Autodesk Fusion 360 part; units mm, degrees
(part 4 of 6)
sketch "Sketch2" plane through (0, 1.5, 0) normal (0, 1, 0) x (-1, 0, 0)
  arc A0 (-68.3, 47.105) -> (-68.05, 46.855) centre (-68.05, 47.105) ccw
  line L0 (-68.05, 46.855) -> (-66.4, 46.855)
  arc A1 (-66.15, 46.605) -> (-66.4, 46.855) centre (-66.4, 46.605) ccw
  line L1 (-66.15, 46.605) -> (-66.15, 42.69)
  line L2 (-66.15, 42.69) -> (-64.15, 42.69)
  line L3 (-64.15, 42.69) -> (-64.15, 46.755)
  arc A2 (-63.9, 47.005) -> (-64.15, 46.755) centre (-63.9, 46.755) ccw
  line L4 (-63.9, 47.005) -> (-50.4, 47.005)
  arc A3 (-50.15, 46.755) -> (-50.4, 47.005) centre (-50.4, 46.755) ccw
  line L5 (-50.15, 46.755) -> (-50.15, 42.69)
  line L6 (-50.15, 42.69) -> (-48.15, 42.69)
  line L7 (-48.15, 42.69) -> (-48.15, 46.605)
  arc A4 (-47.9, 46.855) -> (-48.15, 46.605) centre (-47.9, 46.605) ccw
  line L8 (-47.9, 46.855) -> (-46.25, 46.855)
  arc A5 (-46.25, 46.855) -> (-46, 47.105) centre (-46.25, 47.105) ccw
  line L9 (-46, 47.105) -> (-46, 47.605)
  arc A6 (-45.75, 47.855) -> (-46, 47.605) centre (-45.75, 47.605) ccw
  line L10 (-45.75, 47.855) -> (-44.55, 47.855)
  arc A7 (-44.3, 47.605) -> (-44.55, 47.855) centre (-44.55, 47.605) ccw
  line L11 (-44.3, 47.605) -> (-44.3, 47.105)
  arc A8 (-44.3, 47.105) -> (-44.05, 46.855) centre (-44.05, 47.105) ccw
  line L12 (-44.05, 46.855) -> (-42.4, 46.855)
  arc A9 (-42.15, 46.605) -> (-42.4, 46.855) centre (-42.4, 46.605) ccw
  line L13 (-42.15, 46.605) -> (-42.15, 34.605)
  arc A10 (-42.4, 34.355) -> (-42.15, 34.605) centre (-42.4, 34.605) ccw
  line L14 (-42.4, 34.355) -> (-47.9, 34.355)
  arc A11 (-48.15, 34.605) -> (-47.9, 34.355) centre (-47.9, 34.605) ccw
  line L15 (-48.15, 34.605) -> (-48.15, 40.19)
  line L16 (-48.15, 40.19) -> (-50.15, 40.19)
  line L17 (-50.15, 40.19) -> (-50.15, 33.255)
  arc A12 (-50.4, 33.005) -> (-50.15, 33.255) centre (-50.4, 33.255) ccw
  line L18 (-50.4, 33.005) -> (-63.9, 33.005)
  arc A13 (-64.15, 33.255) -> (-63.9, 33.005) centre (-63.9, 33.255) ccw
  line L19 (-64.15, 33.255) -> (-64.15, 40.19)
  line L20 (-64.15, 40.19) -> (-66.15, 40.19)
  line L21 (-66.15, 40.19) -> (-66.15, 34.605)
  arc A14 (-66.4, 34.355) -> (-66.15, 34.605) centre (-66.4, 34.605) ccw
  line L22 (-66.4, 34.355) -> (-71.9, 34.355)
  arc A15 (-72.15, 34.605) -> (-71.9, 34.355) centre (-71.9, 34.605) ccw
  line L23 (-72.15, 34.605) -> (-72.15, 46.605)
  arc A16 (-71.9, 46.855) -> (-72.15, 46.605) centre (-71.9, 46.605) ccw
  line L24 (-71.9, 46.855) -> (-70.25, 46.855)
  arc A17 (-70.25, 46.855) -> (-70, 47.105) centre (-70.25, 47.105) ccw
  line L25 (-70, 47.105) -> (-70, 47.605)
  arc A18 (-69.75, 47.855) -> (-70, 47.605) centre (-69.75, 47.605) ccw
  line L26 (-69.75, 47.855) -> (-68.55, 47.855)
  arc A19 (-68.3, 47.605) -> (-68.55, 47.855) centre (-68.55, 47.605) ccw
  line L27 (-68.3, 47.605) -> (-68.3, 47.105)
  arc A20 (-73.525, 22.33) -> (-73.775, 22.58) centre (-73.775, 22.33) ccw
  line L28 (-73.775, 22.58) -> (-74.275, 22.58)
  arc A21 (-74.525, 22.83) -> (-74.275, 22.58) centre (-74.275, 22.83) ccw
  line L29 (-74.525, 22.83) -> (-74.525, 24.03)
  arc A22 (-74.275, 24.28) -> (-74.525, 24.03) centre (-74.275, 24.03) ccw
  line L30 (-74.275, 24.28) -> (-73.775, 24.28)
  arc A23 (-73.775, 24.28) -> (-73.525, 24.53) centre (-73.775, 24.53) ccw
  line L31 (-73.525, 24.53) -> (-73.525, 26.18)
  arc A24 (-73.275, 26.43) -> (-73.525, 26.18) centre (-73.275, 26.18) ccw
  line L32 (-73.275, 26.43) -> (-61.275, 26.43)
  arc A25 (-61.025, 26.18) -> (-61.275, 26.43) centre (-61.275, 26.18) ccw
  line L33 (-61.025, 26.18) -> (-61.025, 20.68)
  arc A26 (-61.275, 20.43) -> (-61.025, 20.68) centre (-61.275, 20.68) ccw
  line L34 (-61.275, 20.43) -> (-66.86, 20.43)
  line L35 (-66.86, 20.43) -> (-66.86, 18.43)
  line L36 (-66.86, 18.43) -> (-59.925, 18.43)
  arc A27 (-59.675, 18.18) -> (-59.925, 18.43) centre (-59.925, 18.18) ccw
  line L37 (-59.675, 18.18) -> (-59.675, 4.68)
  arc A28 (-59.925, 4.43) -> (-59.675, 4.68) centre (-59.925, 4.68) ccw
  line L38 (-59.925, 4.43) -> (-66.86, 4.43)
  line L39 (-66.86, 4.43) -> (-66.86, 2.43)
  line L40 (-66.86, 2.43) -> (-61.275, 2.43)
  arc A29 (-61.025, 2.18) -> (-61.275, 2.43) centre (-61.275, 2.18) ccw
  line L41 (-61.025, 2.18) -> (-61.025, -3.32)
  arc A30 (-61.275, -3.57) -> (-61.025, -3.32) centre (-61.275, -3.32) ccw
  line L42 (-61.275, -3.57) -> (-73.275, -3.57)
  arc A31 (-73.525, -3.32) -> (-73.275, -3.57) centre (-73.275, -3.32) ccw
  line L43 (-73.525, -3.32) -> (-73.525, -1.67)
  arc A32 (-73.525, -1.67) -> (-73.775, -1.42) centre (-73.775, -1.67) ccw
  line L44 (-73.775, -1.42) -> (-74.275, -1.42)
  arc A33 (-74.525, -1.17) -> (-74.275, -1.42) centre (-74.275, -1.17) ccw
  line L45 (-74.525, -1.17) -> (-74.525, 0.03)
  arc A34 (-74.275, 0.28) -> (-74.525, 0.03) centre (-74.275, 0.03) ccw
  line L46 (-74.275, 0.28) -> (-73.775, 0.28)
  arc A35 (-73.775, 0.28) -> (-73.525, 0.53) centre (-73.775, 0.53) ccw
  line L47 (-73.525, 0.53) -> (-73.525, 2.18)
  arc A36 (-73.275, 2.43) -> (-73.525, 2.18) centre (-73.275, 2.18) ccw
  line L48 (-73.275, 2.43) -> (-69.36, 2.43)
  line L49 (-69.36, 2.43) -> (-69.36, 4.43)
  line L50 (-69.36, 4.43) -> (-73.425, 4.43)
  arc A37 (-73.675, 4.68) -> (-73.425, 4.43) centre (-73.425, 4.68) ccw
  line L51 (-73.675, 4.68) -> (-73.675, 18.18)
  arc A38 (-73.425, 18.43) -> (-73.675, 18.18) centre (-73.425, 18.18) ccw
  line L52 (-73.425, 18.43) -> (-69.36, 18.43)
  line L53 (-69.36, 18.43) -> (-69.36, 20.43)
  line L54 (-69.36, 20.43) -> (-73.275, 20.43)
  arc A39 (-73.525, 20.68) -> (-73.275, 20.43) centre (-73.275, 20.68) ccw
  line L55 (-73.525, 20.68) -> (-73.525, 22.33)
  arc A40 (30.475, 54.725) -> (30.725, 54.475) centre (30.725, 54.725) ccw
  line L56 (30.725, 54.475) -> (32.375, 54.475)
  arc A41 (32.625, 54.225) -> (32.375, 54.475) centre (32.375, 54.225) ccw
  line L57 (32.625, 54.225) -> (32.625, 50.31)
  line L58 (32.625, 50.31) -> (40.625, 50.31)
  line L59 (40.625, 50.31) -> (40.625, 54.375)
  arc A42 (40.875, 54.625) -> (40.625, 54.375) centre (40.875, 54.375) ccw
  line L60 (40.875, 54.625) -> (54.375, 54.625)
  arc A43 (54.625, 54.375) -> (54.375, 54.625) centre (54.375, 54.375) ccw
  line L61 (54.625, 54.375) -> (54.625, 50.31)
  line L62 (54.625, 50.31) -> (62.625, 50.31)
  line L63 (62.625, 50.31) -> (62.625, 54.225)
  arc A44 (62.875, 54.475) -> (62.625, 54.225) centre (62.875, 54.225) ccw
  line L64 (62.875, 54.475) -> (64.525, 54.475)
  arc A45 (64.525, 54.475) -> (64.775, 54.725) centre (64.525, 54.725) ccw
  line L65 (64.775, 54.725) -> (64.775, 55.225)
  arc A46 (65.025, 55.475) -> (64.775, 55.225) centre (65.025, 55.225) ccw
  line L66 (65.025, 55.475) -> (66.225, 55.475)
  arc A47 (66.475, 55.225) -> (66.225, 55.475) centre (66.225, 55.225) ccw
  line L67 (66.475, 55.225) -> (66.475, 54.725)
  arc A48 (66.475, 54.725) -> (66.725, 54.475) centre (66.725, 54.725) ccw
  line L68 (66.725, 54.475) -> (68.375, 54.475)
  arc A49 (68.625, 54.225) -> (68.375, 54.475) centre (68.375, 54.225) ccw
  line L69 (68.625, 54.225) -> (68.625, 42.225)
  arc A50 (68.375, 41.975) -> (68.625, 42.225) centre (68.375, 42.225) ccw
  line L70 (68.375, 41.975) -> (62.875, 41.975)
  arc A51 (62.625, 42.225) -> (62.875, 41.975) centre (62.875, 42.225) ccw
  line L71 (62.625, 42.225) -> (62.625, 47.81)
  line L72 (62.625, 47.81) -> (54.625, 47.81)
  line L73 (54.625, 47.81) -> (54.625, 40.875)
  arc A52 (54.375, 40.625) -> (54.625, 40.875) centre (54.375, 40.875) ccw
  line L74 (54.375, 40.625) -> (40.875, 40.625)
  arc A53 (40.625, 40.875) -> (40.875, 40.625) centre (40.875, 40.875) ccw
  line L75 (40.625, 40.875) -> (40.625, 47.81)
  line L76 (40.625, 47.81) -> (32.625, 47.81)
  line L77 (32.625, 47.81) -> (32.625, 42.225)
  arc A54 (32.375, 41.975) -> (32.625, 42.225) centre (32.375, 42.225) ccw
  line L78 (32.375, 41.975) -> (26.875, 41.975)
  arc A55 (26.625, 42.225) -> (26.875, 41.975) centre (26.875, 42.225) ccw
  line L79 (26.625, 42.225) -> (26.625, 54.225)
  arc A56 (26.875, 54.475) -> (26.625, 54.225) centre (26.875, 54.225) ccw
  line L80 (26.875, 54.475) -> (28.525, 54.475)
  arc A57 (28.525, 54.475) -> (28.775, 54.725) centre (28.525, 54.725) ccw
  line L81 (28.775, 54.725) -> (28.775, 55.225)
  arc A58 (29.025, 55.475) -> (28.775, 55.225) centre (29.025, 55.225) ccw
  line L82 (29.025, 55.475) -> (30.225, 55.475)
  arc A59 (30.475, 55.225) -> (30.225, 55.475) centre (30.225, 55.225) ccw
  line L83 (30.475, 55.225) -> (30.475, 54.725)
  line L84 (-21.825, 33.005) -> (-35.325, 33.005)
  arc A60 (-35.575, 33.255) -> (-35.325, 33.005) centre (-35.325, 33.255) ccw
  line L85 (-35.575, 33.255) -> (-35.575, 46.755)
  arc A61 (-35.325, 47.005) -> (-35.575, 46.755) centre (-35.325, 46.755) ccw
  line L86 (-35.325, 47.005) -> (-21.825, 47.005)
  arc A62 (-21.575, 46.755) -> (-21.825, 47.005) centre (-21.825, 46.755) ccw
  line L87 (-21.575, 46.755) -> (-21.575, 33.255)
  arc A63 (-21.825, 33.005) -> (-21.575, 33.255) centre (-21.825, 33.255) ccw
  line L88 (43.9638, 101.8458) -> (47.4579, 88.8058)
  arc A64 (47.2811, 88.4996) -> (47.4579, 88.8058) centre (47.2164, 88.7411) ccw
  line L89 (47.2811, 88.4996) -> (34.2411, 85.0056)
  arc A65 (33.9349, 85.1824) -> (34.2411, 85.0056) centre (34.1764, 85.2471) ccw
  line L90 (33.9349, 85.1824) -> (30.4408, 98.2224)
  arc A66 (30.6176, 98.5285) -> (30.4408, 98.2224) centre (30.6823, 98.2871) ccw
  line L91 (30.6176, 98.5285) -> (43.6576, 102.0226)
  arc A67 (43.9638, 101.8458) -> (43.6576, 102.0226) centre (43.7223, 101.7811) ccw
  line L92 (35.325, -22.24) -> (21.825, -22.24)
  arc A68 (21.575, -21.99) -> (21.825, -22.24) centre (21.825, -21.99) ccw
  line L93 (21.575, -21.99) -> (21.575, -8.49)
  arc A69 (21.825, -8.24) -> (21.575, -8.49) centre (21.825, -8.49) ccw
  line L94 (21.825, -8.24) -> (35.325, -8.24)
  arc A70 (35.575, -8.49) -> (35.325, -8.24) centre (35.325, -8.49) ccw
  line L95 (35.575, -8.49) -> (35.575, -21.99)
  arc A71 (35.325, -22.24) -> (35.575, -21.99) centre (35.325, -21.99) ccw
  line L96 (-16.525, -42.945) -> (-16.525, -29.445)
  arc A72 (-16.275, -29.195) -> (-16.525, -29.445) centre (-16.275, -29.445) ccw
  line L97 (-16.275, -29.195) -> (-2.775, -29.195)
  arc A73 (-2.525, -29.445) -> (-2.775, -29.195) centre (-2.775, -29.445) ccw
  line L98 (-2.525, -29.445) -> (-2.525, -42.945)
  arc A74 (-2.775, -43.195) -> (-2.525, -42.945) centre (-2.775, -42.945) ccw
  line L99 (-2.775, -43.195) -> (-16.275, -43.195)
  arc A75 (-16.525, -42.945) -> (-16.275, -43.195) centre (-16.275, -42.945) ccw
  line L100 (-21.825, -24.145) -> (-35.325, -24.145)
  arc A76 (-35.575, -23.895) -> (-35.325, -24.145) centre (-35.325, -23.895) ccw
  line L101 (-35.575, -23.895) -> (-35.575, -10.395)
  arc A77 (-35.325, -10.145) -> (-35.575, -10.395) centre (-35.325, -10.395) ccw
  line L102 (-35.325, -10.145) -> (-21.825, -10.145)
  arc A78 (-21.575, -10.395) -> (-21.825, -10.145) centre (-21.825, -10.395) ccw
  line L103 (-21.575, -10.395) -> (-21.575, -23.895)
  arc A79 (-21.825, -24.145) -> (-21.575, -23.895) centre (-21.825, -23.895) ccw
  line L104 (-40.875, 13.955) -> (-54.375, 13.955)
  arc A80 (-54.625, 14.205) -> (-54.375, 13.955) centre (-54.375, 14.205) ccw
  line L105 (-54.625, 14.205) -> (-54.625, 27.705)
  arc A81 (-54.375, 27.955) -> (-54.625, 27.705) centre (-54.375, 27.705) ccw
  line L106 (-54.375, 27.955) -> (-40.875, 27.955)
  arc A82 (-40.625, 27.705) -> (-40.875, 27.955) centre (-40.875, 27.705) ccw
  line L107 (-40.625, 27.705) -> (-40.625, 14.205)
  arc A83 (-40.875, 13.955) -> (-40.625, 14.205) centre (-40.875, 14.205) ccw
  line L108 (21.575, -60.09) -> (21.575, -46.59)
  arc A84 (21.825, -46.34) -> (21.575, -46.59) centre (21.825, -46.59) ccw
  line L109 (21.825, -46.34) -> (35.325, -46.34)
  arc A85 (35.575, -46.59) -> (35.325, -46.34) centre (35.325, -46.59) ccw
  line L110 (35.575, -46.59) -> (35.575, -60.09)
  arc A86 (35.325, -60.34) -> (35.575, -60.09) centre (35.325, -60.09) ccw
  line L111 (35.325, -60.34) -> (21.825, -60.34)
  arc A87 (21.575, -60.09) -> (21.825, -60.34) centre (21.825, -60.09) ccw
  line L112 (25.5629, 96.9153) -> (29.057, 83.8753)
  arc A88 (28.8802, 83.5691) -> (29.057, 83.8753) centre (28.8155, 83.8106) ccw
  line L113 (28.8802, 83.5691) -> (15.8402, 80.0751)
  arc A89 (15.534, 80.2519) -> (15.8402, 80.0751) centre (15.7755, 80.3166) ccw
  line L114 (15.534, 80.2519) -> (12.0399, 93.2919)
  arc A90 (12.2167, 93.598) -> (12.0399, 93.2919) centre (12.2814, 93.3566) ccw
  line L115 (12.2167, 93.598) -> (25.2567, 97.0921)
  arc A91 (25.5629, 96.9153) -> (25.2567, 97.0921) centre (25.3214, 96.8506) ccw
  line L116 (35.325, 15.86) -> (21.825, 15.86)
  arc A92 (21.575, 16.11) -> (21.825, 15.86) centre (21.825, 16.11) ccw
  line L117 (21.575, 16.11) -> (21.575, 29.61)
  arc A93 (21.825, 29.86) -> (21.575, 29.61) centre (21.825, 29.61) ccw
  line L118 (21.825, 29.86) -> (35.325, 29.86)
  arc A94 (35.575, 29.61) -> (35.325, 29.86) centre (35.325, 29.61) ccw
  line L119 (35.575, 29.61) -> (35.575, 16.11)
  arc A95 (35.325, 15.86) -> (35.575, 16.11) centre (35.325, 16.11) ccw
  line L120 (-59.925, -24.145) -> (-73.425, -24.145)
  arc A96 (-73.675, -23.895) -> (-73.425, -24.145) centre (-73.425, -23.895) ccw
  line L121 (-73.675, -23.895) -> (-73.675, -10.395)
  arc A97 (-73.425, -10.145) -> (-73.675, -10.395) centre (-73.425, -10.395) ccw
  line L122 (-73.425, -10.145) -> (-59.925, -10.145)
  arc A98 (-59.675, -10.395) -> (-59.925, -10.145) centre (-59.925, -10.395) ccw
  line L123 (-59.675, -10.395) -> (-59.675, -23.895)
  arc A99 (-59.925, -24.145) -> (-59.675, -23.895) centre (-59.925, -23.895) ccw
  line L124 (54.375, -54.625) -> (40.875, -54.625)
  arc A100 (40.625, -54.375) -> (40.875, -54.625) centre (40.875, -54.375) ccw
  line L125 (40.625, -54.375) -> (40.625, -40.875)
  arc A101 (40.875, -40.625) -> (40.625, -40.875) centre (40.875, -40.875) ccw
  line L126 (40.875, -40.625) -> (54.375, -40.625)
  arc A102 (54.625, -40.875) -> (54.375, -40.625) centre (54.375, -40.875) ccw
  line L127 (54.625, -40.875) -> (54.625, -54.375)
  arc A103 (54.375, -54.625) -> (54.625, -54.375) centre (54.375, -54.375) ccw
  line L128 (-2.775, -24.145) -> (-16.275, -24.145)
  arc A104 (-16.525, -23.895) -> (-16.275, -24.145) centre (-16.275, -23.895) ccw
  line L129 (-16.525, -23.895) -> (-16.525, -10.395)
  arc A105 (-16.275, -10.145) -> (-16.525, -10.395) centre (-16.275, -10.395) ccw
  line L130 (-16.275, -10.145) -> (-2.775, -10.145)
  arc A106 (-2.525, -10.395) -> (-2.775, -10.145) centre (-2.775, -10.395) ccw
  line L131 (-2.525, -10.395) -> (-2.525, -23.895)
  arc A107 (-2.775, -24.145) -> (-2.525, -23.895) centre (-2.775, -23.895) ccw
  line L132 (-2.775, 13.955) -> (-16.275, 13.955)
  arc A108 (-16.525, 14.205) -> (-16.275, 13.955) centre (-16.275, 14.205) ccw
  line L133 (-16.525, 14.205) -> (-16.525, 27.705)
  arc A109 (-16.275, 27.955) -> (-16.525, 27.705) centre (-16.275, 27.705) ccw
  line L134 (-16.275, 27.955) -> (-2.775, 27.955)
  arc A110 (-2.525, 27.705) -> (-2.775, 27.955) centre (-2.775, 27.705) ccw
  line L135 (-2.525, 27.705) -> (-2.525, 14.205)
  arc A111 (-2.775, 13.955) -> (-2.525, 14.205) centre (-2.775, 14.205) ccw
  line L136 (54.375, -16.525) -> (40.875, -16.525)
  arc A112 (40.625, -16.275) -> (40.875, -16.525) centre (40.875, -16.275) ccw
  line L137 (40.625, -16.275) -> (40.625, -2.775)
  arc A113 (40.875, -2.525) -> (40.625, -2.775) centre (40.875, -2.775) ccw
  line L138 (40.875, -2.525) -> (54.375, -2.525)
  arc A114 (54.625, -2.775) -> (54.375, -2.525) centre (54.375, -2.775) ccw
  line L139 (54.625, -2.775) -> (54.625, -16.275)
  arc A115 (54.375, -16.525) -> (54.625, -16.275) centre (54.375, -16.275) ccw
  line L140 (-2.775, 33.005) -> (-16.275, 33.005)
  arc A116 (-16.525, 33.255) -> (-16.275, 33.005) centre (-16.275, 33.255) ccw
  line L141 (-16.525, 33.255) -> (-16.525, 46.755)
  arc A117 (-16.275, 47.005) -> (-16.525, 46.755) centre (-16.275, 46.755) ccw
  line L142 (-16.275, 47.005) -> (-2.775, 47.005)
  arc A118 (-2.525, 46.755) -> (-2.775, 47.005) centre (-2.775, 46.755) ccw
  line L143 (-2.525, 46.755) -> (-2.525, 33.255)
  arc A119 (-2.775, 33.005) -> (-2.525, 33.255) centre (-2.775, 33.255) ccw
  line L144 (48.8943, 83.4449) -> (52.3884, 70.4049)
  arc A120 (52.2116, 70.0988) -> (52.3884, 70.4049) centre (52.1469, 70.3402) ccw
  line L145 (52.2116, 70.0988) -> (39.1716, 66.6047)
  arc A121 (38.8654, 66.7815) -> (39.1716, 66.6047) centre (39.1069, 66.8462) ccw
  line L146 (38.8654, 66.7815) -> (35.3713, 79.8215)
  arc A122 (35.5481, 80.1277) -> (35.3713, 79.8215) centre (35.6128, 79.8862) ccw
  line L147 (35.5481, 80.1277) -> (48.5881, 83.6217)
  arc A123 (48.8943, 83.4449) -> (48.5881, 83.6217) centre (48.6528, 83.3802) ccw
  line L148 (-59.925, -43.195) -> (-73.425, -43.195)
  arc A124 (-73.675, -42.945) -> (-73.425, -43.195) centre (-73.425, -42.945) ccw
  line L149 (-73.675, -42.945) -> (-73.675, -29.445)
  arc A125 (-73.425, -29.195) -> (-73.675, -29.445) centre (-73.425, -29.445) ccw
  line L150 (-73.425, -29.195) -> (-59.925, -29.195)
  arc A126 (-59.675, -29.445) -> (-59.925, -29.195) centre (-59.925, -29.445) ccw
  line L151 (-59.675, -29.445) -> (-59.675, -42.945)
  arc A127 (-59.925, -43.195) -> (-59.675, -42.945) centre (-59.925, -42.945) ccw
  line L152 (16.275, -14.62) -> (2.775, -14.62)
  arc A128 (2.525, -14.37) -> (2.775, -14.62) centre (2.775, -14.37) ccw
  line L153 (2.525, -14.37) -> (2.525, -0.87)
  arc A129 (2.775, -0.62) -> (2.525, -0.87) centre (2.775, -0.87) ccw
  line L154 (2.775, -0.62) -> (16.275, -0.62)
  arc A130 (16.525, -0.87) -> (16.275, -0.62) centre (16.275, -0.87) ccw
  line L155 (16.525, -0.87) -> (16.525, -14.37)
  arc A131 (16.275, -14.62) -> (16.525, -14.37) centre (16.275, -14.37) ccw
  line L156 (-21.825, 13.955) -> (-35.325, 13.955)
  arc A132 (-35.575, 14.205) -> (-35.325, 13.955) centre (-35.325, 14.205) ccw
  line L157 (-35.575, 14.205) -> (-35.575, 27.705)
  arc A133 (-35.325, 27.955) -> (-35.575, 27.705) centre (-35.325, 27.705) ccw
  line L158 (-35.325, 27.955) -> (-21.825, 27.955)
  arc A134 (-21.575, 27.705) -> (-21.825, 27.955) centre (-21.825, 27.705) ccw
  line L159 (-21.575, 27.705) -> (-21.575, 14.205)
  arc A135 (-21.825, 13.955) -> (-21.575, 14.205) centre (-21.825, 14.205) ccw
  line L160 (-54.625, -4.845) -> (-54.625, 8.655)
  arc A136 (-54.375, 8.905) -> (-54.625, 8.655) centre (-54.375, 8.655) ccw
  line L161 (-54.375, 8.905) -> (-40.875, 8.905)
  arc A137 (-40.625, 8.655) -> (-40.875, 8.905) centre (-40.875, 8.655) ccw
  line L162 (-40.625, 8.655) -> (-40.625, -4.845)
  arc A138 (-40.875, -5.095) -> (-40.625, -4.845) centre (-40.875, -4.845) ccw
  line L163 (-40.875, -5.095) -> (-54.375, -5.095)
  arc A139 (-54.625, -4.845) -> (-54.375, -5.095) centre (-54.375, -4.845) ccw
  line L164 (86.56, 59.625) -> (84.594, 73.5992)
  line L165 (84.594, 73.5992) -> (73.4518, 115.1823)
  line L166 (73.4518, 115.1823) -> (5.8515, 97.0689)
  line L167 (5.8515, 97.0689) -> (2.475, 71.055)
  line L168 (2.475, 71.055) -> (-59.625, 71.055)
  line L169 (-59.625, 71.055) -> (-59.625, 52.005)
  line L170 (-59.625, 52.005) -> (-78.675, 52.005)
  line L171 (-78.675, 52.005) -> (-78.675, -48.195)
  line L172 (-78.675, -48.195) -> (-2.475, -48.195)
  line L173 (-2.475, -48.195) -> (-2.475, -57.72)
  line L174 (-2.475, -57.72) -> (16.575, -57.72)
  line L175 (16.575, -57.72) -> (16.575, -65.34)
  line L176 (16.575, -65.34) -> (40.575, -65.34)
  line L177 (40.575, -65.34) -> (40.575, -59.625)
  line L178 (40.575, -59.625) -> (86.56, -59.625)
  line L179 (86.56, -59.625) -> (86.56, 59.625)
  line L180 (35.325, -41.29) -> (21.825, -41.29)
  arc A140 (21.575, -41.04) -> (21.825, -41.29) centre (21.825, -41.04) ccw
  line L181 (21.575, -41.04) -> (21.575, -27.54)
  arc A141 (21.825, -27.29) -> (21.575, -27.54) centre (21.825, -27.54) ccw
  line L182 (21.825, -27.29) -> (35.325, -27.29)
  arc A142 (35.575, -27.54) -> (35.325, -27.29) centre (35.325, -27.54) ccw
  line L183 (35.575, -27.54) -> (35.575, -41.04)
  arc A143 (35.325, -41.29) -> (35.575, -41.04) centre (35.325, -41.04) ccw
  line L184 (16.275, 23.48) -> (2.775, 23.48)
  arc A144 (2.525, 23.73) -> (2.775, 23.48) centre (2.775, 23.73) ccw
  line L185 (2.525, 23.73) -> (2.525, 37.23)
  arc A145 (2.775, 37.48) -> (2.525, 37.23) centre (2.775, 37.23) ccw
  line L186 (2.775, 37.48) -> (16.275, 37.48)
  arc A146 (16.525, 37.23) -> (16.275, 37.48) centre (16.275, 37.23) ccw
  line L187 (16.525, 37.23) -> (16.525, 23.73)
  arc A147 (16.275, 23.48) -> (16.525, 23.73) centre (16.275, 23.73) ccw
  line L188 (-2.775, -5.095) -> (-16.275, -5.095)
  arc A148 (-16.525, -4.845) -> (-16.275, -5.095) centre (-16.275, -4.845) ccw
  line L189 (-16.525, -4.845) -> (-16.525, 8.655)
  arc A149 (-16.275, 8.905) -> (-16.525, 8.655) centre (-16.275, 8.655) ccw
  line L190 (-16.275, 8.905) -> (-2.775, 8.905)
  arc A150 (-2.525, 8.655) -> (-2.775, 8.905) centre (-2.775, 8.655) ccw
  line L191 (-2.525, 8.655) -> (-2.525, -4.845)
  arc A151 (-2.775, -5.095) -> (-2.525, -4.845) centre (-2.775, -4.845) ccw
  line L192 (-21.825, -5.095) -> (-35.325, -5.095)
  arc A152 (-35.575, -4.845) -> (-35.325, -5.095) centre (-35.325, -4.845) ccw
  line L193 (-35.575, -4.845) -> (-35.575, 8.655)
  arc A153 (-35.325, 8.905) -> (-35.575, 8.655) centre (-35.325, 8.655) ccw
  line L194 (-35.325, 8.905) -> (-21.825, 8.905)
  arc A154 (-21.575, 8.655) -> (-21.825, 8.905) centre (-21.825, 8.655) ccw
  line L195 (-21.575, 8.655) -> (-21.575, -4.845)
  arc A155 (-21.825, -5.095) -> (-21.575, -4.845) centre (-21.825, -4.845) ccw
  line L196 (73.425, 21.575) -> (59.925, 21.575)
  arc A156 (59.675, 21.825) -> (59.925, 21.575) centre (59.925, 21.825) ccw
  line L197 (59.675, 21.825) -> (59.675, 35.325)
  arc A157 (59.925, 35.575) -> (59.675, 35.325) centre (59.925, 35.325) ccw
  line L198 (59.925, 35.575) -> (73.425, 35.575)
  arc A158 (73.675, 35.325) -> (73.425, 35.575) centre (73.425, 35.325) ccw
  line L199 (73.675, 35.325) -> (73.675, 21.825)
  arc A159 (73.425, 21.575) -> (73.675, 21.825) centre (73.425, 21.825) ccw
  line L200 (73.425, -16.525) -> (59.925, -16.525)
  arc A160 (59.675, -16.275) -> (59.925, -16.525) centre (59.925, -16.275) ccw
  line L201 (59.675, -16.275) -> (59.675, -2.775)
  arc A161 (59.925, -2.525) -> (59.675, -2.775) centre (59.925, -2.775) ccw
  line L202 (59.925, -2.525) -> (73.425, -2.525)
  arc A162 (73.675, -2.775) -> (73.425, -2.525) centre (73.425, -2.775) ccw
  line L203 (73.675, -2.775) -> (73.675, -16.275)
  arc A163 (73.425, -16.525) -> (73.675, -16.275) centre (73.425, -16.275) ccw
  line L204 (54.375, 21.575) -> (40.875, 21.575)
  arc A164 (40.625, 21.825) -> (40.875, 21.575) centre (40.875, 21.825) ccw
  line L205 (40.625, 21.825) -> (40.625, 35.325)
  arc A165 (40.875, 35.575) -> (40.625, 35.325) centre (40.875, 35.325) ccw
  line L206 (40.875, 35.575) -> (54.375, 35.575)
  arc A166 (54.625, 35.325) -> (54.375, 35.575) centre (54.375, 35.325) ccw
  line L207 (54.625, 35.325) -> (54.625, 21.825)
  arc A167 (54.375, 21.575) -> (54.625, 21.825) centre (54.375, 21.825) ccw
  line L208 (-54.625, -42.945) -> (-54.625, -29.445)
  arc A168 (-54.375, -29.195) -> (-54.625, -29.445) centre (-54.375, -29.445) ccw
  line L209 (-54.375, -29.195) -> (-40.875, -29.195)
  arc A169 (-40.625, -29.445) -> (-40.875, -29.195) centre (-40.875, -29.445) ccw
  line L210 (-40.625, -29.445) -> (-40.625, -42.945)
  arc A170 (-40.875, -43.195) -> (-40.625, -42.945) centre (-40.875, -42.945) ccw
  line L211 (-40.875, -43.195) -> (-54.375, -43.195)
  arc A171 (-54.625, -42.945) -> (-54.375, -43.195) centre (-54.375, -42.945) ccw
  line L212 (2.525, -52.47) -> (2.525, -38.72)
  line L213 (2.525, -38.72) -> (16.275, -38.72)
  arc A172 (16.525, -38.97) -> (16.275, -38.72) centre (16.275, -38.97) ccw
  line L214 (16.525, -38.97) -> (16.525, -52.47)
  arc A173 (16.275, -52.72) -> (16.525, -52.47) centre (16.275, -52.47) ccw
  line L215 (16.275, -52.72) -> (2.775, -52.72)
  arc A174 (2.525, -52.47) -> (2.775, -52.72) centre (2.775, -52.47) ccw
  line L216 (54.375, 2.525) -> (40.875, 2.525)
  arc A175 (40.625, 2.775) -> (40.875, 2.525) centre (40.875, 2.775) ccw
  line L217 (40.625, 2.775) -> (40.625, 16.275)
  arc A176 (40.875, 16.525) -> (40.625, 16.275) centre (40.875, 16.275) ccw
  line L218 (40.875, 16.525) -> (54.375, 16.525)
  arc A177 (54.625, 16.275) -> (54.375, 16.525) centre (54.375, 16.275) ccw
  line L219 (54.625, 16.275) -> (54.625, 2.775)
  arc A178 (54.375, 2.525) -> (54.625, 2.775) centre (54.375, 2.775) ccw
  line L220 (16.275, 42.53) -> (2.775, 42.53)
  arc A179 (2.525, 42.78) -> (2.775, 42.53) centre (2.775, 42.78) ccw
  line L221 (2.525, 42.78) -> (2.525, 56.28)
  arc A180 (2.775, 56.53) -> (2.525, 56.28) centre (2.775, 56.28) ccw
  line L222 (2.775, 56.53) -> (16.275, 56.53)
  arc A181 (16.525, 56.28) -> (16.275, 56.53) centre (16.275, 56.28) ccw
  line L223 (16.525, 56.28) -> (16.525, 42.78)
  arc A182 (16.275, 42.53) -> (16.525, 42.78) centre (16.275, 42.78) ccw
  line L224 (73.425, 2.525) -> (59.925, 2.525)
  arc A183 (59.675, 2.775) -> (59.925, 2.525) centre (59.925, 2.775) ccw
  line L225 (59.675, 2.775) -> (59.675, 16.275)
  arc A184 (59.925, 16.525) -> (59.675, 16.275) centre (59.925, 16.275) ccw
  line L226 (59.925, 16.525) -> (73.425, 16.525)
  arc A185 (73.675, 16.275) -> (73.425, 16.525) centre (73.425, 16.275) ccw
  line L227 (73.675, 16.275) -> (73.675, 2.775)
  arc A186 (73.425, 2.525) -> (73.675, 2.775) centre (73.425, 2.775) ccw
  line L228 (20.4645, 61.851) -> (16.9705, 74.891)
  arc A187 (17.1472, 75.1972) -> (16.9705, 74.891) centre (17.2119, 74.9557) ccw
  line L229 (17.1472, 75.1972) -> (30.1872, 78.6912)
  arc A188 (30.4934, 78.5144) -> (30.1872, 78.6912) centre (30.2519, 78.4497) ccw
  line L230 (30.4934, 78.5144) -> (33.9875, 65.4744)
  arc A189 (33.8107, 65.1683) -> (33.9875, 65.4744) centre (33.746, 65.4097) ccw
  line L231 (33.8107, 65.1683) -> (20.7707, 61.6742)
  arc A190 (20.4645, 61.851) -> (20.7707, 61.6742) centre (20.706, 61.9157) ccw
  line L232 (-21.825, 52.055) -> (-35.325, 52.055)
  arc A191 (-35.575, 52.305) -> (-35.325, 52.055) centre (-35.325, 52.305) ccw
  line L233 (-35.575, 52.305) -> (-35.575, 65.805)
  arc A192 (-35.325, 66.055) -> (-35.575, 65.805) centre (-35.325, 65.805) ccw
  line L234 (-35.325, 66.055) -> (-21.825, 66.055)
  arc A193 (-21.575, 65.805) -> (-21.825, 66.055) centre (-21.825, 65.805) ccw
  line L235 (-21.575, 65.805) -> (-21.575, 52.305)
  arc A194 (-21.825, 52.055) -> (-21.575, 52.305) centre (-21.825, 52.305) ccw
  line L236 (35.325, -3.19) -> (21.825, -3.19)
  arc A195 (21.575, -2.94) -> (21.825, -3.19) centre (21.825, -2.94) ccw
  line L237 (21.575, -2.94) -> (21.575, 10.56)
  arc A196 (21.825, 10.81) -> (21.575, 10.56) centre (21.825, 10.56) ccw
  line L238 (21.825, 10.81) -> (35.325, 10.81)
  arc A197 (35.575, 10.56) -> (35.325, 10.81) centre (35.325, 10.56) ccw
  line L239 (35.575, 10.56) -> (35.575, -2.94)
  arc A198 (35.325, -3.19) -> (35.575, -2.94) centre (35.325, -2.94) ccw
  line L240 (-21.825, -43.195) -> (-35.325, -43.195)
  arc A199 (-35.575, -42.945) -> (-35.325, -43.195) centre (-35.325, -42.945) ccw
  line L241 (-35.575, -42.945) -> (-35.575, -29.445)
  arc A200 (-35.325, -29.195) -> (-35.575, -29.445) centre (-35.325, -29.445) ccw
  line L242 (-35.325, -29.195) -> (-21.825, -29.195)
  arc A201 (-21.575, -29.445) -> (-21.825, -29.195) centre (-21.825, -29.445) ccw
  line L243 (-21.575, -29.445) -> (-21.575, -42.945)
  arc A202 (-21.825, -43.195) -> (-21.575, -42.945) centre (-21.825, -42.945) ccw
  line L244 (59.675, -54.375) -> (59.675, -40.875)
  arc A203 (59.925, -40.625) -> (59.675, -40.875) centre (59.925, -40.875) ccw
  line L245 (59.925, -40.625) -> (73.425, -40.625)
  arc A204 (73.675, -40.875) -> (73.425, -40.625) centre (73.425, -40.875) ccw
  line L246 (73.675, -40.875) -> (73.675, -54.375)
  arc A205 (73.425, -54.625) -> (73.675, -54.375) centre (73.425, -54.375) ccw
  line L247 (73.425, -54.625) -> (59.925, -54.625)
  arc A206 (59.675, -54.375) -> (59.925, -54.625) centre (59.925, -54.375) ccw
  line L248 (16.275, 4.43) -> (2.775, 4.43)
  arc A207 (2.525, 4.68) -> (2.775, 4.43) centre (2.775, 4.68) ccw
  line L249 (2.525, 4.68) -> (2.525, 18.18)
  arc A208 (2.775, 18.43) -> (2.525, 18.18) centre (2.775, 18.18) ccw
  line L250 (2.775, 18.43) -> (16.275, 18.43)
  arc A209 (16.525, 18.18) -> (16.275, 18.43) centre (16.275, 18.18) ccw
  line L251 (16.525, 18.18) -> (16.525, 4.68)
  arc A210 (16.275, 4.43) -> (16.525, 4.68) centre (16.275, 4.68) ccw
  line L252 (16.275, -33.67) -> (2.775, -33.67)
  arc A211 (2.525, -33.42) -> (2.775, -33.67) centre (2.775, -33.42) ccw
  line L253 (2.525, -33.42) -> (2.525, -19.92)
  arc A212 (2.775, -19.67) -> (2.525, -19.92) centre (2.775, -19.92) ccw
  line L254 (2.775, -19.67) -> (16.275, -19.67)
  arc A213 (16.525, -19.92) -> (16.275, -19.67) centre (16.275, -19.92) ccw
  line L255 (16.525, -19.92) -> (16.525, -33.42)
  arc A214 (16.275, -33.67) -> (16.525, -33.42) centre (16.275, -33.42) ccw
  line L256 (-2.775, 52.055) -> (-16.275, 52.055)
  arc A215 (-16.525, 52.305) -> (-16.275, 52.055) centre (-16.275, 52.305) ccw
  line L257 (-16.525, 52.305) -> (-16.525, 65.805)
  arc A216 (-16.275, 66.055) -> (-16.525, 65.805) centre (-16.275, 65.805) ccw
  line L258 (-16.275, 66.055) -> (-2.775, 66.055)
  arc A217 (-2.525, 65.805) -> (-2.775, 66.055) centre (-2.775, 65.805) ccw
  line L259 (-2.525, 65.805) -> (-2.525, 52.305)
  arc A218 (-2.775, 52.055) -> (-2.525, 52.305) centre (-2.775, 52.305) ccw
  line L260 (54.375, -35.575) -> (40.875, -35.575)
  arc A219 (40.625, -35.325) -> (40.875, -35.575) centre (40.875, -35.325) ccw
  line L261 (40.625, -35.325) -> (40.625, -21.825)
  arc A220 (40.875, -21.575) -> (40.625, -21.825) centre (40.875, -21.825) ccw
  line L262 (40.875, -21.575) -> (54.375, -21.575)
  arc A221 (54.625, -21.825) -> (54.375, -21.575) centre (54.375, -21.825) ccw
  line L263 (54.625, -21.825) -> (54.625, -35.325)
  arc A222 (54.375, -35.575) -> (54.625, -35.325) centre (54.375, -35.325) ccw
  line L264 (67.2952, 88.3754) -> (70.7892, 75.3354)
  arc A223 (70.6125, 75.0293) -> (70.7892, 75.3354) centre (70.5478, 75.2707) ccw
  line L265 (70.6125, 75.0293) -> (57.5725, 71.5352)
  arc A224 (57.2663, 71.712) -> (57.5725, 71.5352) centre (57.5078, 71.7767) ccw
  line L266 (57.2663, 71.712) -> (53.7722, 84.752)
  arc A225 (53.949, 85.0582) -> (53.7722, 84.752) centre (54.0137, 84.8167) ccw
  line L267 (53.949, 85.0582) -> (66.989, 88.5522)
  arc A226 (67.2952, 88.3754) -> (66.989, 88.5522) centre (67.0537, 88.3107) ccw
  line L268 (-40.875, -24.145) -> (-54.375, -24.145)
  arc A227 (-54.625, -23.895) -> (-54.375, -24.145) centre (-54.375, -23.895) ccw
  line L269 (-54.625, -23.895) -> (-54.625, -10.395)
  arc A228 (-54.375, -10.145) -> (-54.625, -10.395) centre (-54.375, -10.395) ccw
  line L270 (-54.375, -10.145) -> (-40.875, -10.145)
  arc A229 (-40.625, -10.395) -> (-40.875, -10.145) centre (-40.875, -10.395) ccw
  line L271 (-40.625, -10.395) -> (-40.625, -23.895)
  arc A230 (-40.875, -24.145) -> (-40.625, -23.895) centre (-40.875, -23.895) ccw
  line L272 (-54.625, 52.305) -> (-54.625, 65.805)
  arc A231 (-54.375, 66.055) -> (-54.625, 65.805) centre (-54.375, 65.805) ccw
  line L273 (-54.375, 66.055) -> (-40.875, 66.055)
  arc A232 (-40.625, 65.805) -> (-40.875, 66.055) centre (-40.875, 65.805) ccw
  line L274 (-40.625, 65.805) -> (-40.625, 52.305)
  arc A233 (-40.875, 52.055) -> (-40.625, 52.305) centre (-40.875, 52.305) ccw
  line L275 (-40.875, 52.055) -> (-54.375, 52.055)
  arc A234 (-54.625, 52.305) -> (-54.375, 52.055) centre (-54.375, 52.305) ccw
  line L276 (73.425, -35.575) -> (59.925, -35.575)
  arc A235 (59.675, -35.325) -> (59.925, -35.575) centre (59.925, -35.325) ccw
  line L277 (59.675, -35.325) -> (59.675, -21.825)
  arc A236 (59.925, -21.575) -> (59.675, -21.825) centre (59.925, -21.825) ccw
  line L278 (59.925, -21.575) -> (73.425, -21.575)
  arc A237 (73.675, -21.825) -> (73.425, -21.575) centre (73.425, -21.825) ccw
  line L279 (73.675, -21.825) -> (73.675, -35.325)
  arc A238 (73.425, -35.575) -> (73.675, -35.325) centre (73.425, -35.325) ccw
  line L280 (62.3647, 106.7763) -> (65.8587, 93.7363)
  arc A239 (65.682, 93.4301) -> (65.8587, 93.7363) centre (65.6173, 93.6716) ccw
  line L281 (65.682, 93.4301) -> (52.642, 89.9361)
  arc A240 (52.3358, 90.1129) -> (52.642, 89.9361) centre (52.5773, 90.1776) ccw
  line L282 (52.3358, 90.1129) -> (48.8417, 103.1529)
  arc A241 (49.0185, 103.459) -> (48.8417, 103.1529) centre (49.0832, 103.2176) ccw
  line L283 (49.0185, 103.459) -> (62.0585, 106.9531)
  arc A242 (62.3647, 106.7763) -> (62.0585, 106.9531) centre (62.1232, 106.7116) ccw
  line L284 (86.56, -59.625) -> (57.15, -59.625) construction
  line L285 (57.15, -59.625) -> (57.15, -38.1) construction
  line L286 (-78.675, -48.195) -> (-57.15, -48.195) construction
  line L287 (-57.15, -48.195) -> (-57.15, -26.67) construction
  line L288 (-78.675, 52.005) -> (-78.675, 49.53) construction
  line L289 (-78.675, 49.53) -> (-38.1, 49.53) construction
  line L290 (-2.475, -57.72) -> (0.55, -57.72) construction
  line L291 (0.55, -57.72) -> (0.55, 1.905) construction
  line L292 (86.56, 59.625) -> (70.125, 59.625) construction
  line L293 (70.125, 59.625) -> (70.125, 65.125) construction
  line L294 (2.475, 71.055) -> (8.3344, 71.055) construction
  line L295 (8.3344, 71.055) -> (8.3344, 65.0081) construction
  circle A243 centre (70.125, 65.125) radius 1.025
  circle A244 centre (70.125, 65.125) radius 1.75
  circle A245 centre (8.3344, 65.0081) radius 1.025
  circle A246 centre (8.3344, 65.0081) radius 1.75
  circle A247 centre (-38.1, 49.53) radius 1.025
  circle A248 centre (-38.1, 49.53) radius 1.75
  circle A249 centre (-57.15, -26.67) radius 1.025
  circle A250 centre (-57.15, -26.67) radius 1.75
  circle A251 centre (0.55, 1.905) radius 1.025
  circle A252 centre (0.55, 1.905) radius 1.75
  circle A253 centre (57.15, -38.1) radius 1.025
  circle A254 centre (57.15, -38.1) radius 1.75
  dimension "d217" = 29.41
  dimension "d218" = 21.525
  dimension "d219" = 21.525
  dimension "d220" = 21.525
  dimension "d221" = 2.475
  dimension "d222" = 40.575
  dimension "d223" = 3.025
  dimension "d224" = 59.625
  dimension "d225" = 16.435
  dimension "d226" = 5.5
  dimension "d227" = 5.8594
  dimension "d228" = 6.0469
  dimension "d229" = 2.05
  dimension "d230" = 3.5
  dimension "d231" = 2.05
  dimension "d232" = 3.5
  dimension "d233" = 2.05
  dimension "d234" = 3.5
  dimension "d235" = 2.05
  dimension "d236" = 3.5
  dimension "d237" = 2.05
  dimension "d238" = 3.5
  dimension "d239" = 2.05
  dimension "d240" = 3.5
  constraint coincident L178.end L179.start
  constraint coincident L178 L284.end
  constraint perpendicular L178 L285
  constraint coincident L171.end L172.start
  constraint coincident L172 L286.end
  constraint perpendicular L172 L287
  constraint coincident L170.end L171.start
  constraint perpendicular L170 L288
  constraint perpendicular L288 L289
  constraint coincident L173.end L174.start
  constraint coincident L174 L290.end
  constraint perpendicular L174 L291
  constraint coincident L164.start L179.end
  constraint perpendicular L179 L292
  constraint perpendicular L292 L293
  constraint coincident L167.end L168.start
  constraint parallel L168 L294
  constraint perpendicular L168 L295
  constraint coincident L293.end A243.centre
  constraint coincident L295.end A245.centre
  constraint coincident L289.end A247.centre
  constraint coincident L287.end A249.centre
  constraint coincident L291.end A251.centre
  constraint coincident L285.end A253.centre
  measures "d217" distance of L178.end L284.end
  measures "d218" distance of L284.end L285.end
  measures "d219" distance of L171.end L286.end
  measures "d220" distance of L286.end L287.end
  measures "d221" distance of L170.end L288.end
  measures "d222" distance of L288.end L289.end
  measures "d223" distance of L173.end L290.end
  measures "d224" distance of L290.end L291.end
  measures "d225" distance of L164.start L292.end
  measures "d226" distance of L292.end L293.end
  measures "d227" distance of L167.end L294.end
  measures "d228" distance of L294.end L295.end
  measures "d229" diameter of A243
  measures "d230" diameter of A244
  measures "d231" diameter of A245
  measures "d232" diameter of A246
  measures "d233" diameter of A247
  measures "d234" diameter of A248
  measures "d235" diameter of A249
  measures "d236" diameter of A250
  measures "d237" diameter of A251
  measures "d238" diameter of A252
  measures "d239" diameter of A253
  measures "d240" diameter of A254
extrude "Extrude2" [suppressed]
extrude "Extrude3" [suppressed]
equation "sw_size_Ref_Ref = 19.05 mm"
equation "sw_cut_size_Ref_Ref = 14 mm"
equation "sw_cut_space_Ref_Ref = sw_size_Ref_Ref - sw_cut_size_Ref_Ref"
equation "stab_cut_length_Ref_Ref = 6 mm"
equation "stab_cut_height_Ref_Ref = 12.5 mm"
equation "stabw_length_Ref_Ref = 12 mm" comment "Length of the stabilizer wire per unit (e.g. a 2u stabilizer will be stabilizer_wire_length * 2)"
equation "stabw_height_Ref_Ref = 2.5 mm"
equation "stabw_cut_length_Ref_Ref = 1.7 mm"
equation "stabw_cut_height_Ref_Ref = 1 mm"
equation "plt_thickness_Ref_Ref = 1.5 mm"
equation "plt_fillet_Ref_Ref = 0.25 mm"
equation "pcb_thickness_Ref_Ref = 1.6 mm"
equation "m2scr_diameter_Ref_Ref = 2.05 mm"
equation "mtscr_head_diameter_Ref_Ref = 3.5 mm"
equation "mtscr_head_width_Ref_Ref = 0.5 mm"
equation "ctrl_length_Ref_Ref = 33 mm"
equation "ctrl_height_Ref_Ref = 18 mm"
equation "ctrl_width_Ref_Ref = 1.7 mm"
equation "usbc_length_Ref_Ref = 8.34 mm"
equation "usbc_height_Ref_Ref = 2.56 mm"
equation "bat_length_Ref_Ref = 50 mm"
equation "bat_height_Ref_Ref = 34 mm"
equation "bat_width_Ref_Ref = 5 mm"
equation "bat_clearance_Ref_Ref = 3 mm"
equation "key_size_Ref_Ref = 16.5 mm"
equation "key_clearance_Ref_Ref = 0.25 mm"
equation "key_space_Ref_Ref = sw_size_Ref_Ref - ( key_size_Ref_Ref + key_clearance_Ref_Ref )"
equation "key_fillet_Ref_Ref = 1 mm"
equation "thrins_diameter_Ref_Ref = 3.5 mm"
equation "thrins_depth_Ref_Ref = 2.5 mm"
equation "top_inner_thickness_Ref_Ref = 1.5 mm"
equation "plt_up_clearance_Ref_Ref = 4.9 mm"
equation "alignh_diameter_Ref_Ref = 2.5 mm"
equation "alignh_height_Ref_Ref = 5 mm"
equation "case_border_width_Ref_Ref = 10 mm"
equation "col_mid_offset_Ref_Ref = 0.3 * sw_size_Ref_Ref"
equation "col_ring_offset_Ref_Ref = 0.4 * sw_size_Ref_Ref"
equation "col_pinky_offset_Ref_Ref = 0.5 * sw_size_Ref_Ref"
equation "stab_vert_offset_Ref_Ref = 0.6 mm"
equation "stabw_cut_offset_Ref_Ref = 0.835 mm"
equation "plt_border_width_Ref_Ref = 2.475 mm"
equation "case_top_thickness_Ref_Ref = 4 mm"
equation "top_align_mark_length_Ref_Ref = 10 mm"
equation "pcb_clearance_Ref_Ref = 8.5 mm"
equation "case_bot_min_thickness_Ref_Ref = 3 mm"
equation "case_max_length_Ref_Ref = max(7 * sw_size_Ref_Ref + plt_border_width_Ref_Ref * 2 + case_border_width_Ref_Ref * 2; 8 * sw_size_Ref_Ref + ( plt_border_width_Ref_Ref + case_border_width_Ref_Ref ) * 2 + 7.885 mm)"
equation "case_bot_angle_Ref_Ref = 2.75 deg"
equation "case_bot_max_thickness_Ref_Ref = case_max_length_Ref_Ref / tan(90 deg - case_bot_angle_Ref_Ref) + case_bot_min_thickness_Ref_Ref"
equation "ctrl_socket_height_Ref_Ref = 4.191 mm"
equation "bat_wall_thickness_Ref_Ref = 2.5 mm"
equation "bat_offset_Ref_Ref = 25 mm + bat_wall_thickness_Ref_Ref + bat_length_Ref_Ref * 0.5"
equation "sw_hotswap_clearance_Ref_Ref = 1.9 mm"
equation "case_side_fillet_Ref_Ref = 2.5 mm"
equation "case_top_fillet_Ref_Ref = 0.5 mm"
equation "case_top_inner_border_side_fillet_Ref_Ref = 1.5 mm"
equation "case_top_inner_border_top_fillet_Ref_Ref = 1 mm"
equation "usbc_contour_height_Ref_Ref = 4.5 mm"
equation "usbc_contour_length_Ref_Ref = 12 mm"
equation "assemblyscr_head_diameter_Ref_Ref = 4.15 mm"
equation "assemblyscr_head_width_Ref_Ref = 0.85 mm"
equation "rf_diameter_Ref_Ref = 10 mm"
equation "rf_width_Ref_Ref = 0.5 mm"
equation "rf_voffset_Ref_Ref = case_border_width_Ref_Ref + 10 mm"
equation "rf_hoffset_Ref_Ref = case_border_width_Ref_Ref + 15 mm"
equation "ctrl_extension_width_Ref = 7.885 mm"
equation "d67 = sw_size_Ref_Ref * 6"
equation "d68 = sw_size_Ref_Ref * 2"
equation "d69 = col_mid_offset_Ref_Ref"
equation "d70 = sw_size_Ref_Ref"
equation "d71 = col_ring_offset_Ref_Ref"
equation "d72 = sw_size_Ref_Ref"
equation "d73 = col_pinky_offset_Ref_Ref"
equation "d74 = sw_size_Ref_Ref"
equation "d75 = sw_size_Ref_Ref"
equation "d76 = sw_size_Ref_Ref"
equation "d77 = sw_size_Ref_Ref"
equation "d78 = sw_size_Ref_Ref * 5"
equation "d79 = sw_size_Ref_Ref - col_ring_offset_Ref_Ref"
equation "d80 = sw_size_Ref_Ref * 4"
equation "d81 = sw_size_Ref_Ref - col_pinky_offset_Ref_Ref"
equation "d82 = sw_size_Ref_Ref * 5"
equation "d83 = sw_size_Ref_Ref"
equation "d84 = sw_size_Ref_Ref"
equation "d85 = sw_size_Ref_Ref * 6"
equation "d86 = sw_size_Ref_Ref * 2"
equation "d87 = sw_size_Ref_Ref"
equation "d88 = sw_size_Ref_Ref"
equation "d89 = sw_size_Ref_Ref"
equation "d90 = sw_size_Ref_Ref"
equation "d91 = sw_size_Ref_Ref"
equation "d92 = sw_size_Ref_Ref * 2"
equation "d95 = ( sw_size_Ref_Ref - 18 mm ) * 0.5"
equation "d96 = ( sw_size_Ref_Ref - 18 mm ) * 0.5"
equation "d97 = sw_size_Ref_Ref"
equation "d98 = sw_size_Ref_Ref"
equation "d99 = sw_size_Ref_Ref * 2"
equation "d100 = sw_size_Ref_Ref * 2"
equation "d101 = sw_size_Ref_Ref * 3"
equation "d102 = sw_cut_size_Ref_Ref"
equation "d103 = sw_cut_size_Ref_Ref"
equation "d106 = -sw_size_Ref_Ref"
equation "d107 = sw_size_Ref_Ref"
equation "d108 = sw_cut_size_Ref_Ref"
equation "d109 = sw_cut_size_Ref_Ref"
equation "d110 = sw_cut_size_Ref_Ref"
equation "d111 = sw_cut_size_Ref_Ref"
equation "d112 = sw_cut_size_Ref_Ref"
equation "d113 = sw_cut_size_Ref_Ref"
equation "d114 = sw_cut_size_Ref_Ref"
equation "d115 = sw_cut_size_Ref_Ref"
equation "d116 = sw_cut_size_Ref_Ref"
equation "d117 = sw_cut_size_Ref_Ref"
equation "d118 = sw_cut_size_Ref_Ref"
equation "d119 = sw_cut_size_Ref_Ref"
equation "d120 = sw_cut_size_Ref_Ref"
equation "d121 = sw_cut_size_Ref_Ref"
equation "d122 = sw_cut_size_Ref_Ref"
equation "d123 = sw_cut_size_Ref_Ref"
equation "d124 = sw_cut_size_Ref_Ref"
equation "d125 = sw_cut_size_Ref_Ref"
equation "d128 = sw_size_Ref_Ref"
equation "d129 = -sw_size_Ref_Ref"
equation "d133 = -sw_size_Ref_Ref"
equation "d137 = -sw_size_Ref_Ref"
equation "d140 = sw_size_Ref_Ref"
equation "d141 = -sw_size_Ref_Ref"
equation "d144 = sw_size_Ref_Ref"
equation "d145 = -sw_size_Ref_Ref"
equation "d149 = -sw_size_Ref_Ref"
equation "d150 = sw_cut_size_Ref_Ref"
equation "d151 = sw_cut_size_Ref_Ref"
equation "d152 = stab_vert_offset_Ref_Ref"
equation "d153 = stabw_length_Ref_Ref * 1.5"
equation "d154 = stab_cut_length_Ref_Ref"
equation "d155 = stab_cut_height_Ref_Ref"
equation "d156 = stabw_cut_offset_Ref_Ref"
equation "d157 = stabw_height_Ref_Ref * 0.5"
equation "d158 = stabw_cut_length_Ref_Ref * 0.5"
equation "d159 = stabw_cut_length_Ref_Ref"
equation "d160 = stabw_cut_height_Ref_Ref"
equation "d161 = stab_vert_offset_Ref_Ref"
equation "d162 = stabw_length_Ref_Ref"
equation "d163 = stab_cut_length_Ref_Ref"
equation "d164 = stab_cut_height_Ref_Ref"
equation "d165 = stabw_cut_offset_Ref_Ref"
equation "d166 = stabw_height_Ref_Ref * 0.5"
equation "d167 = stabw_cut_length_Ref_Ref * 0.5"
equation "d168 = stabw_cut_length_Ref_Ref"
equation "d169 = stabw_cut_height_Ref_Ref"
equation "d170 = stab_vert_offset_Ref_Ref"
equation "d171 = stabw_length_Ref_Ref"
equation "d172 = stab_cut_height_Ref_Ref"
equation "d173 = stab_cut_length_Ref_Ref"
equation "d174 = stabw_cut_offset_Ref_Ref"
equation "d175 = stabw_height_Ref_Ref * 0.5"
equation "d176 = stabw_cut_length_Ref_Ref * 0.5"
equation "d177 = stabw_cut_height_Ref_Ref"
equation "d178 = stabw_cut_length_Ref_Ref"
equation "d179 = plt_border_width_Ref_Ref + ctrl_extension_width_Ref"
equation "d180 = plt_border_width_Ref_Ref"
equation "d181 = plt_border_width_Ref_Ref"
equation "d182 = plt_border_width_Ref_Ref"
equation "d183 = plt_border_width_Ref_Ref"
equation "d184 = plt_border_width_Ref_Ref"
equation "d185 = plt_border_width_Ref_Ref"
equation "d186 = plt_border_width_Ref_Ref"
equation "d187 = plt_border_width_Ref_Ref"
equation "d188 = plt_border_width_Ref_Ref"
equation "d189 = plt_border_width_Ref_Ref"
equation "d190 = plt_border_width_Ref_Ref"
equation "d191 = plt_border_width_Ref_Ref"
equation "d192 = plt_border_width_Ref_Ref"
equation "d193 = plt_border_width_Ref_Ref"
equation "d194 = plt_border_width_Ref_Ref"
equation "d195 = plt_border_width_Ref_Ref"
equation "d196 = plt_border_width_Ref_Ref"
equation "d197 = plt_border_width_Ref_Ref"
equation "d198 = plt_border_width_Ref_Ref"
equation "d199 = plt_border_width_Ref_Ref"
equation "d200 = plt_border_width_Ref_Ref"
equation "d201 = plt_border_width_Ref_Ref"
equation "d202 = plt_border_width_Ref_Ref"
equation "d203 = plt_border_width_Ref_Ref"
equation "d204 = plt_border_width_Ref_Ref"
equation "d205 = plt_border_width_Ref_Ref + ctrl_extension_width_Ref"
equation "d206 = plt_border_width_Ref_Ref"
equation "d207 = plt_border_width_Ref_Ref + ctrl_extension_width_Ref"
equation "d208 = plt_border_width_Ref_Ref"
equation "d209 = plt_border_width_Ref_Ref"
equation "d210 = plt_border_width_Ref_Ref + ctrl_extension_width_Ref"
equation "d211 = plt_thickness_Ref_Ref"
equation "d214 = plt_fillet_Ref_Ref"
equation "pcase_max_length_Ref = sw_size_Ref_Ref * 8 + ( plt_border_width_Ref_Ref + case_border_width_Ref_Ref ) * 2 + ctrl_extension_width_Ref"
equation "d217 = plt_border_width_Ref_Ref + ctrl_extension_width_Ref + sw_size_Ref_Ref"
equation "d218 = plt_border_width_Ref_Ref + sw_size_Ref_Ref"
equation "d219 = plt_border_width_Ref_Ref + sw_size_Ref_Ref"
equation "d220 = plt_border_width_Ref_Ref + sw_size_Ref_Ref"
equation "d221 = plt_border_width_Ref_Ref"
equation "d222 = plt_border_width_Ref_Ref + sw_size_Ref_Ref * 2"
equation "d223 = plt_border_width_Ref_Ref + 0.55 mm"
equation "d224 = plt_border_width_Ref_Ref + sw_size_Ref_Ref * 3"
equation "d225 = plt_border_width_Ref_Ref + ctrl_extension_width_Ref + 6.075 mm"
equation "d226 = 7.975 mm - plt_border_width_Ref_Ref"
equation "d227 = 8.334375 mm - plt_border_width_Ref_Ref"
equation "d228 = 3.571875 mm + plt_border_width_Ref_Ref"
equation "d229 = m2scr_diameter_Ref_Ref"
equation "d230 = mtscr_head_diameter_Ref_Ref"
equation "d231 = m2scr_diameter_Ref_Ref"
equation "d232 = mtscr_head_diameter_Ref_Ref"
equation "d233 = m2scr_diameter_Ref_Ref"
equation "d234 = mtscr_head_diameter_Ref_Ref"
equation "d235 = m2scr_diameter_Ref_Ref"
equation "d236 = mtscr_head_diameter_Ref_Ref"
equation "d237 = m2scr_diameter_Ref_Ref"
equation "d238 = mtscr_head_diameter_Ref_Ref"
equation "d239 = m2scr_diameter_Ref_Ref"
equation "d240 = mtscr_head_diameter_Ref_Ref"
equation "d242 = -mtscr_head_width_Ref_Ref"

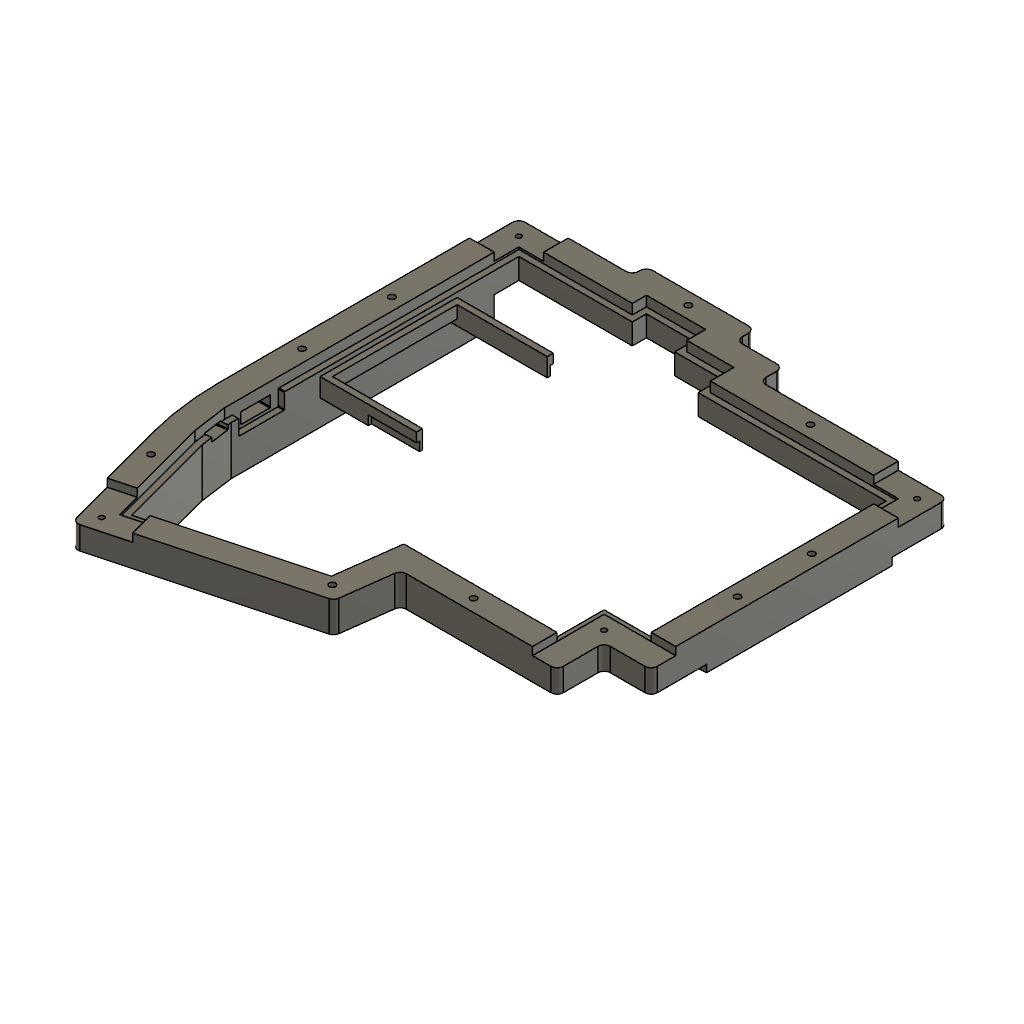
design "Case Wall (Pollux)" references "_Base (Pollux)"
part number: 2026-10-19-10-22-46-059
Autodesk Fusion 360 part; units mm, degrees
derive "Derived from _Base (Pollux)"